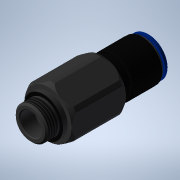
# Autodesk Inventor part: 186283 QSR-G3/8-12
Saved by Autodesk Inventor 2021 (Build 250183000, 183)
## iProperties
Created: 2025-06-04
Part Number: 186283 QSR-G3/8-12
Material: Generic
Catalog Web Link: www.cadenas.de
Description: QSR-G-rotary push-in fitting
Vendor: FESTO
Document SubType Name: Modeling
Designer: psAdmin
Manufacturer: FESTO
Mass: 78 g
Surface Area: 73.3649 cm^2
Volume: 18.7428 cm^3
Density: 1 g/cm^3
Appearance: PSOLRGB-175-175-175
Category: PARTsolutions
Company: FESTO
Title: 186283 QSR-G3/8-12
Author: Cadenas PARTsolutions
Comments: rotary push-in fitting
PSOL_IDENT_0: {$CADENAS_DATA/23d-libs/festo/parts/q/qsr/qsr_g.prj},176 {VTYP=3D},{NB=186283 QSR-G3/8-12},{LINA=186
PSOL_IDENT_1: 283 QSR-G3/8-12},{NN=QSR-G},{DATE=02.05.2025 12:52:42},{GEOMDATE=01.04.2025 10:00:43},{VERSION=},{LI
PSOL_IDENT_2: NEID=100},{WBVAR=},{WBNUMERIC=}  {NB=186283 QSR-G3/8-12},{LINA=186283 QSR-G3/8-12},{KT=2},{TNR=18628
PSOL_IDENT_3: 3},{TYP=QSR-G3/8-12},{D1=G3/8},{NENN=8.000},{D2=12.000},{D5=21.000},{L1=60.700},{L2=6.600},{SW=24.00
PSOL_IDENT_4: 0},{T=23.000},{CNSMASSEXACT=0.0780},{Z=19.800},{NDR=16.662},{VER=2.000},{GH=2.400},{GD=20.000},{GTIN=
PSOL_IDENT_5: 4052568076078},{REACH=Ja},{REACHSVHC=Ja},{REACHHAZSUBS=7439-92-1},{REACHSCIP=90efc32a-c8f2-432f-9110
PSOL_IDENT_6: -007a8bf45910},{REACHVALDATE=05.03.2025}
NB: 186283 QSR-G3/8-12
NN: QSR-G
NT: rotary push-in fitting
NBSYN: $TNR. $TYP.
LINA: 186283 QSR-G3/8-12
CATALOG: Festo
TNR: 186283
TYP: QSR-G3/8-12
D1: G3/8
NENN: 8
D2: 12
D5: 21
L1: 60.7
L2: 6.6
SW: 24
T: 23
CNSMASSEXACT: 0.078
GTIN: 4052568076078
REACH: Yes
REACHSVHC: Yes
REACHHAZSUBS: 7439-92-1
REACHVALDATE: 05.03.2025
SUPPLIER: FESTO
ARTICLENO: 186283 QSR-G3/8-12
BOMINFO: 186283 QSR-G3/8-12
CREATOR: CADENAS GmbH
Autodesk Inventor part; units mm, degrees
ref_plane "YZ Plane" through (0, 0, 0) normal (1, 0, 0) x (0, 1, 0)
ref_plane "XZ Plane" through (0, 0, 0) normal (0, 1, 0) x (-1, 0, 0)
ref_plane "XY Plane" through (0, 0, 0) normal (0, 0, 1) x (1, 0, 0)
sketch "Sketch_1" plane through (0, 0, 0) normal (1, 0, 0) x (0, 1, 0)
  line L0 (0, 0) -> (0, 6.6)
  line L1 (0, 6.6) -> (7.475, 6.6)
  line L2 (7.475, 6.6) -> (8.331, 5.744)
  line L3 (8.331, 5.744) -> (8.331, 0)
  line L4 (8.331, 0) -> (0, 0)
  line L5 (0, 0) -> (0, 6.6)
  constraints: 12 end point
revolve "Revolution1" add sketch "Sketch_1" angle 360 about axis through (0, 0, 0) along (0, 0, -1)
thread "Thread1" size "G16.662x1.337" designation "G 3/8" class "A" standard "ISO Pipe Threads" length 4.744
sketch "Sketch_2" plane through (0, 0, 0) normal (1, 0, 0) x (0, 1, 0)
  line L0 (0, -54.1) -> (0, 0)
  line L1 (0, 0) -> (10, 0)
  line L2 (10, 0) -> (10, -2.4)
  line L3 (10, -2.4) -> (12, -2.4)
  line L4 (12, -2.4) -> (13.2, -4.4785)
  line L5 (13.2, -4.4785) -> (13.2, -28.0215)
  line L6 (13.2, -28.0215) -> (12, -30.1)
  line L7 (12, -30.1) -> (10.2, -30.1)
  line L8 (10.2, -30.1) -> (10.2, -30.6)
  line L9 (10.2, -30.6) -> (10.5, -30.6)
  line L10 (10.5, -30.6) -> (10.5, -33.1)
  line L11 (10.5, -33.1) -> (9.45, -33.7062)
  line L12 (9.45, -33.7062) -> (9.45, -35.1)
  line L13 (9.45, -35.1) -> (10.1, -35.1)
  line L14 (10.1, -35.1) -> (10.5, -35.5)
  line L15 (10.5, -35.5) -> (10.5, -48.7)
  line L16 (10.5, -48.7) -> (10.3951, -50.2)
  line L17 (10.3951, -50.2) -> (9.9, -50.2)
  line L18 (9.9, -50.2) -> (9.9, -50.55)
  line L19 (9.9, -50.55) -> (9.8, -50.65)
  line L20 (9.8, -50.65) -> (9.9, -50.75)
  line L21 (9.9, -50.75) -> (9.9, -51.1)
  line L22 (9.9, -51.1) -> (9.8, -51.2)
  line L23 (9.8, -51.2) -> (6.7, -51.2)
  line L24 (6.7, -51.2) -> (6.7, -51.8)
  arc A0 (6.7, -51.8) -> (7, -52.1) centre (7, -51.8) ccw
  line L25 (7, -52.1) -> (9.9, -52.1)
  line L26 (9.9, -52.1) -> (9.9, -53.2974)
  arc A1 (9.7347, -53.4944) -> (9.9, -53.2974) centre (9.7, -53.2974) ccw
  line L27 (9.7347, -53.4944) -> (6.3, -54.1)
  line L28 (6.3, -54.1) -> (0, -54.1)
  line L29 (0, -54.1) -> (0, 0)
  constraints: 60 end point, 4 point on circle, 2 centre point
revolve "Revolution2" add sketch "Sketch_2" angle 360 about axis through (0, 0, -54.1) along (0, 0, -1)
sketch "Sketch_5" plane through (0, 0, -35.5) normal (0, 0, 1) x (1, 0, 0)
  arc A0 (-10.4732, 0.75) -> (-10.4732, -0.75) centre (0, 0) ccw
  line L0 (-10.4732, -0.75) -> (10.4732, -0.75)
  arc A1 (10.4732, -0.75) -> (10.4732, 0.75) centre (0, 0) ccw
  line L1 (10.4732, 0.75) -> (-10.4732, 0.75)
  constraints: 4 end point, 4 point on circle, 2 centre point
extrude "Extrusion1" add sketch "Sketch_5" along normal blind 2.4
sketch "Sketch_7" plane through (0, 0, -2.4) normal (0, 0, 1) x (1, 0, 0)
  line L0 (-24, -24) -> (24, -24)
  line L1 (24, -24) -> (24, 24)
  line L2 (24, 24) -> (-24, 24)
  line L3 (-24, 24) -> (-24, -24)
  line L4 (-12, -6.9282) -> (0, -13.8564)
  line L5 (0, -13.8564) -> (12, -6.9282)
  line L6 (12, -6.9282) -> (12, 6.9282)
  line L7 (12, 6.9282) -> (0, 13.8564)
  line L8 (0, 13.8564) -> (-12, 6.9282)
  line L9 (-12, 6.9282) -> (-12, -6.9282)
  constraints: 20 end point
extrude "Extrusion2" cut sketch "Sketch_7" against normal blind 27.7
sketch "Sketch_4" plane through (0, 0, 0) normal (1, 0, 0) x (0, 1, 0)
  line L0 (0, -54.1) -> (0, 6.6)
  line L1 (0, 6.6) -> (5.9783, 6.6)
  line L2 (5.9783, 6.6) -> (5.554, 6.1757)
  line L3 (5.554, 6.1757) -> (5.554, -1)
  line L4 (5.554, -1) -> (4, -1.8972)
  line L5 (4, -1.8972) -> (4, -31.1)
  line L6 (4, -31.1) -> (6, -31.1)
  line L7 (6, -31.1) -> (6, -53.8)
  arc A0 (6, -53.8) -> (6.3, -54.1) centre (6.3, -53.8) ccw
  line L8 (6.3, -54.1) -> (0, -54.1)
  line L9 (0, -54.1) -> (0, 6.6)
  constraints: 20 end point, 2 point on circle, 1 centre point
revolve "Revolution3" cut sketch "Sketch_4" angle 360 about axis through (0, 0, -54.1) along (0, 0, -1)
body "Solid1"
